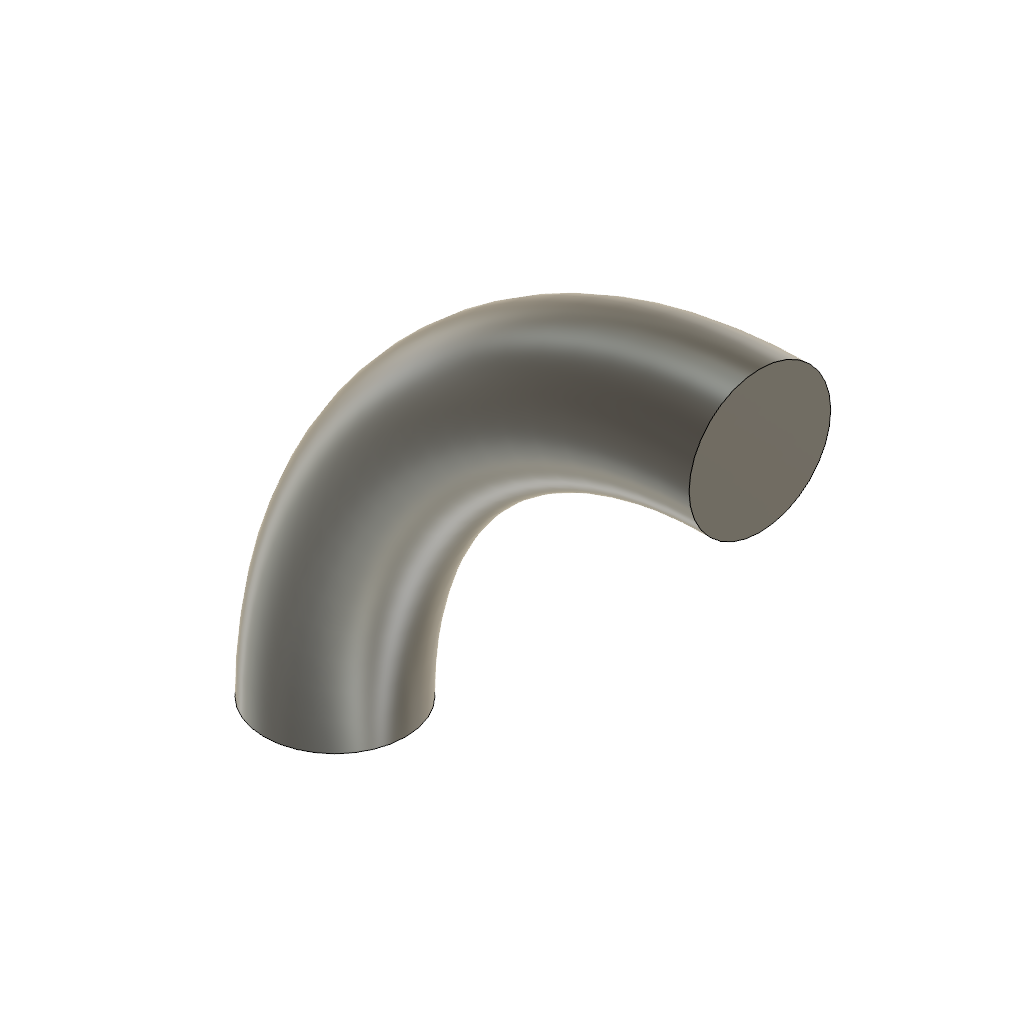
Sweep (Autodesk Fusion 360 design; units mm, degrees)
part number: 2026-11-12-11-46-39-390
Autodesk Fusion 360 part; units mm, degrees
sketch "Sweep profile" plane through (0, 0, 0) normal (0, 0, 1) x (1, 0, 0)
  circle A0 centre (0, 0) radius 5
sketch "Sweep path" plane through (0, 0, 0) normal (0, 1, 0) x (1, 0, 0)
  arc A0 (0, 0) -> (30, -30) centre (30, 0) ccw
sweep "Arc sweep" add profiles "Sweep profile" path "Sweep path" along A0 section 1
